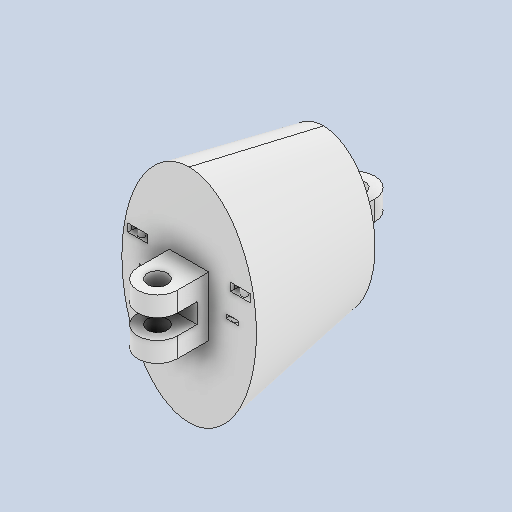
# Autodesk Inventor part: tail_segment_3
Saved by Autodesk Inventor 2026.1 (Build 301233020, 233B)
## iProperties
Created: 2025-11-11
Part Number: tail_segment_3
Material: Plastica ABS
Document SubType Name: Modeling
Designer: maxbu
Density: 1.06 g/cm^3
Appearance: Liscia - Bianco
Mass: 42.7276 g
Surface Area: 78.8538 cm^2
Volume: 40.309 cm^3
Author: maxbu
Autodesk Inventor part; units mm, degrees
ref_plane "YZ Plane" through (0, 0, 0) normal (1, 0, 0) x (0, 1, 0)
sketch "Schizzo1" plane through (0, 0, 0) normal (1, 0, 0) x (0, 1, 0)
  line L0 (0, 0) -> (0, -5) construction
  line L1 (0, -5) -> (2.5, -5)
  line L2 (2.5, -5) -> (2.5, 5)
  line L3 (2.5, 5) -> (7.5, 5)
  line L4 (7.5, 5) -> (7.5, -8)
  line L5 (7.5, -8) -> (0, -8)
  line L6 (0, -5) -> (-2.5, -5)
  line L7 (-2.5, -5) -> (-2.5, 5)
  line L8 (-2.5, 5) -> (-7.5, 5)
  line L9 (-7.5, 5) -> (-7.5, -8)
  line L10 (-7.5, -8) -> (0, -8)
  line L11 (0, -8) -> (0, -42) construction
  line L12 (0, -42) -> (2.5, -42)
  line L13 (2.5, -42) -> (2.5, -55)
  line L14 (2.5, -55) -> (-2.5, -55)
  line L15 (-2.5, -55) -> (-2.5, -42)
  line L16 (-2.5, -42) -> (0, -42)
  line L17 (0, -42) -> (0, -50) construction
  dimension "d22" = 5
  dimension "d25" = 8
  dimension "d27" = 10
  dimension "d28" = 5
  dimension "d29" = 5
  dimension "d30" = 8
  dimension "d31" = 50
  dimension "d32" = 5
  dimension "d33" = 5
  constraints: 36 end point, 8 perpendicular, 4 symmetric about line, 2 collinear, 2 horizontal, 2 point on line, 2 vertical, 1 coincident
  measures "d22" distance of L0.start L0.end
  measures "d25" distance from line of L12 L17.end
  measures "d27" distance of L1.end L2.end
  measures "d28" distance between parallel lines of L7 L2
  measures "d29" distance of L2.end L3.end
  measures "d30" distance from line of L10 L0.start
  measures "d31" distance of L17.end L0.start
  measures "d32" distance of L13.end L14.end
  measures "d33" distance from line of L17.end L14
extrude "Estrusione1" add sketch "Schizzo1" along normal mid plane 10
sketch "Schizzo2" plane through (5, 7.5, -8) normal (0, 0, -1) x (-1, 0, 0)
  line L0 (5, -7.5) -> (5, -7.5) construction
  ellipse E0 centre (5, -7.5) end of major axis (5, 20.5) minor radius 17
  dimension "d2" = 28
  dimension "d3" = 17
  dimension "d4" = 0
  constraints: 2 end point, 1 coincident, 1 vertical, 2 other
  measures "d4" distance of L0.start L0.end
ref_plane "Piano di lavoro2" through (0, 0, -25) normal (0, 0, 1) x (1, 0, 0)
sketch "Schizzo4" plane through (0, 0, -25) normal (0, 0, 1) x (1, 0, 0)
  line L0 (0, 0) -> (0, 0) construction
  line L1 (-5, -2.5) -> (5, -2.5) projected
  ellipse E0 centre (0, 0) end of major axis (0, 24) minor radius 15
  dimension "d11" = 15
  dimension "d12" = 24
  dimension "d10" = 0
  constraints: 2 end point, 1 coincident, 1 perpendicular, 2 other
  measures "d10" distance of L0.start L0.end
sketch "Schizzo5" plane through (-5, -2.5, -42) normal (0, 0, 1) x (1, 0, 0)
  line L0 (5, 2.5) -> (5, 2.5) construction
  line L1 (0, 0) -> (10, 0) projected
  ellipse E0 centre (5, 2.5) end of major axis (5, 22.5) minor radius 13
  dimension "d14" = 13
  dimension "d15" = 20
  dimension "d13" = 0
  constraints: 2 end point, 1 coincident, 1 perpendicular, 2 other
  measures "d13" distance of L0.start L0.end
loft "Loft1" add profiles "Schizzo2", "Schizzo4", "Schizzo5"
fillet "Raccordo2" radius 5 6 edges at (-5, 5, 5) (5, 5, 5) (-5, -5, 5) (5, -5, 5) (5, 0, -55) (-5, 0, -55)
sketch "Schizzo8" plane through (-5, 7.5, -8) normal (0, 1, 0) x (1, 0, 0)
  arc A0 (10, 42) -> (0, 42) centre (5, 42) ccw projected
  point P0 (5, -8)
  constraints: 1 coincident
hole "Foro1" at (0, 7.5, -50) at (0, 7.5, 0) direction (0, -1, 0) diameter 5 end through all
sketch "Schizzo9" plane through (0, 0, 0) normal (0, 1, 0) x (-1, 0, 0)
  line L0 (13, -42) -> (-13, -42) construction
  line L1 (-9, -42) -> (-12, -8)
  line L2 (17, -8) -> (-17, -8) projected
  line L3 (-10.0039, -42) -> (-13.0039, -8)
  line L4 (-13.0039, -8) -> (-12.0078, -7.9121)
  line L5 (-12.0078, -7.9121) -> (-12, -8)
  line L6 (-10.0039, -42) -> (-9.9884, -42.1758)
  line L7 (-9, -42) -> (-8.9922, -42.0879)
  line L8 (-9.9884, -42.1758) -> (-8.9922, -42.0879)
  line L9 (-8.9922, -42.0879) -> (-7.9961, -42) construction
  point P0 (0, 0)
  point P1 (0, -42)
  point P2 (0, -8)
  point P3 (0, -42)
  point P4 (0, -8)
  dimension "d49" = 9
  dimension "d50" = 12
  dimension "d51" = 1
  constraints: 17 end point, 5 collinear, 5 point on line, 2 midpoint, 2 perpendicular, 1 parallel
  measures "d49" distance of L1.start point (0, -42)
  measures "d50" distance of L1.end point (0, -8)
  measures "d51" distance between parallel lines of L1 L3
revolve "Rivoluzione1" [suppressed]
mirror "Speculare1" [suppressed]
fillet "Raccordo3" [suppressed]
ref_plane "Piano di lavoro3" through (0, 7, 0) normal (0, 1, 0) x (-1, 0, 0)
sketch "Schizzo10" plane through (0, 7, 0) normal (0, 1, 0) x (-1, 0, 0)
  circle A0 centre (-13, -9) radius 0.75
  arc A1 (-15.5, -9) -> (-10.5, -9) centre (-13, -9) ccw
  line L0 (17, -8) -> (-17, -8) projected
  line L1 (-15.5, -9) -> (-15.5, -8)
  line L2 (-10.5, -9) -> (-10.5, -8)
  line L3 (-10.5, -8) -> (-15.5, -8)
  point P0 (0, 0)
  point P1 (0, -8)
  point P2 (0, -8)
  point P3 (-14, -8)
  dimension "d54" = 1.5
  dimension "d55" = 5
  dimension "d56" = 1
  dimension "d57" = 13
  constraints: 6 end point, 2 centre point, 2 perpendicular, 2 point on circle, 2 point on line, 2 tangent, 1 coincident, 1 collinear, 1 midpoint
  measures "d54" diameter of A0
  measures "d55" diameter of A1
  measures "d56" distance of L1.start L1.end
  measures "d57" horizontal distance of point (0, -8) A0.centre
extrude "Estrusione3" cut sketch "Schizzo10" along normal mid plane 2
mirror "Speculare2" about plane through (0, 0, 0) normal (1, 0, 0) of "Estrusione3"
sketch "Schizzo11" plane through (0, 0, 0) normal (0, 1, 0) x (-1, 0, 0)
  circle A0 centre (11, -8.7) radius 0.7
  line L0 (17, -8) -> (-17, -8) projected
  circle A1 centre (11, -8.7) radius 1.7
  circle A2 centre (9, -41.3) radius 0.7
  line L1 (13, -42) -> (-13, -42) projected
  circle A3 centre (9, -41.3) radius 1.7
  point P0 (0, 0)
  point P1 (0, -8)
  point P2 (0, -8)
  point P3 (9.4508, -8)
  point P4 (12.5492, -8)
  point P5 (11, -8)
  point P6 (0, -42)
  point P7 (0, -42)
  point P8 (10.5492, -42)
  point P9 (7.4508, -42)
  point P10 (9, -42)
  dimension "d61" = 1.4
  dimension "d62" = 1
  dimension "d63" = 11
  dimension "d66" = 1
  dimension "d67" = 1.4
  dimension "d68" = 9
  constraints: 4 centre point, 2 coincident, 2 midpoint, 2 tangent
  measures "d61" diameter of A0
  measures "d62" radial gap between concentric circles of A0 A1
  measures "d63" horizontal distance of point (0, -8) A0.centre
  measures "d66" radial gap between concentric circles of A3 A2
  measures "d67" diameter of A2
  measures "d68" horizontal distance of point (0, -42) A2.centre
extrude "Estrusione4" cut sketch "Schizzo11" along normal mid plane 1 contours L0 A1 | L1 A3 picked at (12.3507, -8.8334) picked at (10.3507, -41.1666)
mirror "Speculare3" about plane through (0, 0, 0) normal (1, 0, 0) of "Estrusione4"
